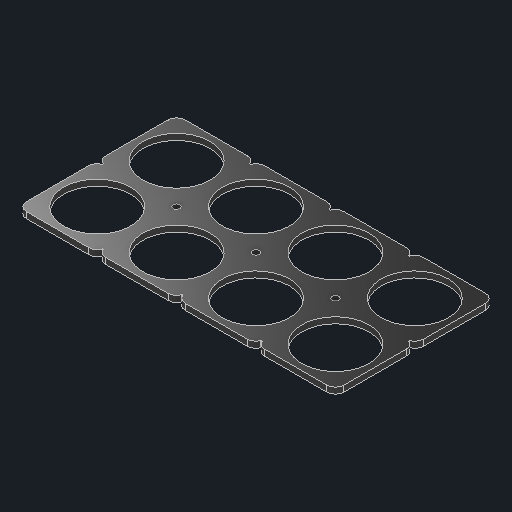
# Autodesk Inventor part: ProductsStoringGrid
Saved by Autodesk Inventor 2027.1 (Build 311270010, 270A)
## iProperties
Created: 2026-09-29
Part Number: ProductsStoringGrid
Material: MDF Medium Density Fiberboard
Document SubType Name: Modeling
Designer: SDS Scholar
Density: 0.8 g/cm^3
Appearance: Glossy - Black
Mass: 55.351 g
Surface Area: 384.534 cm^2
Volume: 69.1887 cm^3
Author: SDS Scholar
Autodesk Inventor part; units mm, degrees
ref_plane "YZ Plane" through (0, 0, 0) normal (1, 0, 0) x (0, 1, 0)
ref_plane "XZ Plane" through (0, 0, 0) normal (0, 1, 0) x (-1, 0, 0)
ref_plane "XY Plane" through (0, 0, 0) normal (0, 0, 1) x (1, 0, 0)
sketch "Sketch1" plane through (0, 0, 0) normal (0, 1, 0) x (-1, 0, 0)
  line L0 (118, 60) -> (77, 60)
  line L1 (70, 53) -> (70, 12)
  line L2 (77, 5) -> (118, 5)
  line L3 (125, 12) -> (125, 53)
  line L4 (123, 65) -> (72, 65)
  line L5 (65, 58) -> (65, 7)
  line L6 (72, 0) -> (123, 0)
  line L7 (130, 7) -> (130, 58)
  arc A0 (130, 58) -> (123, 65) centre (123, 58) ccw
  arc A1 (123, 0) -> (130, 7) centre (123, 7) ccw
  arc A2 (118, 5) -> (125, 12) centre (118, 12) ccw
  arc A3 (125, 53) -> (118, 60) centre (118, 53) ccw
  arc A4 (77, 60) -> (70, 53) centre (77, 53) ccw
  arc A5 (70, 12) -> (77, 5) centre (77, 12) ccw
  arc A6 (65, 7) -> (72, 0) centre (72, 7) ccw
  arc A7 (72, 65) -> (65, 58) centre (72, 58) ccw
  line L8 (0, 100) -> (0, -100) construction
  line L9 (100, 0) -> (-100, 0) construction
  line L10 (70, -12) -> (70, -53)
  line L11 (77, -60) -> (118, -60)
  line L12 (65, -7) -> (65, -58)
  arc A8 (77, -5) -> (70, -12) centre (77, -12) ccw
  line L13 (72, -65) -> (123, -65)
  arc A9 (72, 0) -> (65, -7) centre (72, -7) ccw
  line L14 (118, -5) -> (77, -5)
  line L15 (123, 0) -> (72, 0)
  arc A10 (130, -7) -> (123, 0) centre (123, -7) ccw
  arc A11 (65, -58) -> (72, -65) centre (72, -58) ccw
  arc A12 (70, -53) -> (77, -60) centre (77, -53) ccw
  line L16 (125, -53) -> (125, -12)
  line L17 (130, -58) -> (130, -7)
  arc A13 (125, -12) -> (118, -5) centre (118, -12) ccw
  arc A14 (118, -60) -> (125, -53) centre (118, -53) ccw
  arc A15 (123, -65) -> (130, -58) centre (123, -58) ccw
  line L18 (12, 5) -> (53, 5)
  line L19 (60, 12) -> (60, 53)
  line L20 (7, 0) -> (58, 0)
  line L21 (65, 7) -> (65, 58)
  arc A16 (5, 12) -> (12, 5) centre (12, 12) ccw
  line L22 (0, 58) -> (0, 7)
  line L23 (5, 53) -> (5, 12)
  arc A17 (60, 53) -> (53, 60) centre (53, 53) ccw
  arc A18 (65, 58) -> (58, 65) centre (58, 58) ccw
  line L24 (53, 60) -> (12, 60)
  line L25 (58, 65) -> (7, 65)
  arc A19 (53, 5) -> (60, 12) centre (53, 12) ccw
  arc A20 (7, 65) -> (0, 58) centre (7, 58) ccw
  arc A21 (12, 60) -> (5, 53) centre (12, 53) ccw
  arc A22 (58, 0) -> (65, 7) centre (58, 7) ccw
  arc A23 (0, 7) -> (7, 0) centre (7, 7) ccw
  line L26 (5, -12) -> (5, -53)
  line L27 (0, -7) -> (0, -58)
  arc A24 (5, -53) -> (12, -60) centre (12, -53) ccw
  arc A25 (0, -58) -> (7, -65) centre (7, -58) ccw
  line L28 (53, -5) -> (12, -5)
  line L29 (58, 0) -> (7, 0)
  arc A26 (60, -12) -> (53, -5) centre (53, -12) ccw
  arc A27 (65, -7) -> (58, 0) centre (58, -7) ccw
  line L30 (60, -53) -> (60, -12)
  line L31 (65, -58) -> (65, -7)
  line L32 (12, -60) -> (53, -60)
  line L33 (7, -65) -> (58, -65)
  arc A28 (53, -60) -> (60, -53) centre (53, -53) ccw
  arc A29 (12, -5) -> (5, -12) centre (12, -12) ccw
  arc A30 (58, -65) -> (65, -58) centre (58, -58) ccw
  arc A31 (7, 0) -> (0, -7) centre (7, -7) ccw
  line L34 (-53, 5) -> (-12, 5)
  line L35 (-5, 12) -> (-5, 53)
  line L36 (-58, 0) -> (-7, 0)
  line L37 (0, 7) -> (0, 58)
  arc A32 (-60, 12) -> (-53, 5) centre (-53, 12) ccw
  line L38 (-65, 58) -> (-65, 7)
  line L39 (-60, 53) -> (-60, 12)
  arc A33 (-5, 53) -> (-12, 60) centre (-12, 53) ccw
  arc A34 (0, 58) -> (-7, 65) centre (-7, 58) ccw
  line L40 (-12, 60) -> (-53, 60)
  line L41 (-7, 65) -> (-58, 65)
  arc A35 (-12, 5) -> (-5, 12) centre (-12, 12) ccw
  arc A36 (-58, 65) -> (-65, 58) centre (-58, 58) ccw
  arc A37 (-53, 60) -> (-60, 53) centre (-53, 53) ccw
  arc A38 (-7, 0) -> (0, 7) centre (-7, 7) ccw
  arc A39 (-65, 7) -> (-58, 0) centre (-58, 7) ccw
  line L42 (-60, -12) -> (-60, -53)
  line L43 (-65, -7) -> (-65, -58)
  arc A40 (-60, -53) -> (-53, -60) centre (-53, -53) ccw
  arc A41 (-65, -58) -> (-58, -65) centre (-58, -58) ccw
  line L44 (-12, -5) -> (-53, -5)
  line L45 (-7, 0) -> (-58, 0)
  arc A42 (-5, -12) -> (-12, -5) centre (-12, -12) ccw
  arc A43 (0, -7) -> (-7, 0) centre (-7, -7) ccw
  line L46 (-5, -53) -> (-5, -12)
  line L47 (0, -58) -> (0, -7)
  line L48 (-53, -60) -> (-12, -60)
  line L49 (-58, -65) -> (-7, -65)
  arc A44 (-12, -60) -> (-5, -53) centre (-12, -53) ccw
  arc A45 (-53, -5) -> (-60, -12) centre (-53, -12) ccw
  arc A46 (-7, -65) -> (0, -58) centre (-7, -58) ccw
  arc A47 (-58, 0) -> (-65, -7) centre (-58, -7) ccw
  line L50 (-118, 5) -> (-77, 5)
  line L51 (-70, 12) -> (-70, 53)
  line L52 (-123, 0) -> (-72, 0)
  line L53 (-65, 7) -> (-65, 58)
  arc A48 (-125, 12) -> (-118, 5) centre (-118, 12) ccw
  line L54 (-130, 58) -> (-130, 7)
  line L55 (-125, 53) -> (-125, 12)
  arc A49 (-70, 53) -> (-77, 60) centre (-77, 53) ccw
  arc A50 (-65, 58) -> (-72, 65) centre (-72, 58) ccw
  line L56 (-77, 60) -> (-118, 60)
  line L57 (-72, 65) -> (-123, 65)
  arc A51 (-77, 5) -> (-70, 12) centre (-77, 12) ccw
  arc A52 (-123, 65) -> (-130, 58) centre (-123, 58) ccw
  arc A53 (-118, 60) -> (-125, 53) centre (-118, 53) ccw
  arc A54 (-72, 0) -> (-65, 7) centre (-72, 7) ccw
  arc A55 (-130, 7) -> (-123, 0) centre (-123, 7) ccw
  line L58 (-125, -12) -> (-125, -53)
  line L59 (-130, -7) -> (-130, -58)
  arc A56 (-125, -53) -> (-118, -60) centre (-118, -53) ccw
  arc A57 (-130, -58) -> (-123, -65) centre (-123, -58) ccw
  line L60 (-77, -5) -> (-118, -5)
  line L61 (-72, 0) -> (-123, 0)
  arc A58 (-70, -12) -> (-77, -5) centre (-77, -12) ccw
  arc A59 (-65, -7) -> (-72, 0) centre (-72, -7) ccw
  line L62 (-70, -53) -> (-70, -12)
  line L63 (-65, -58) -> (-65, -7)
  line L64 (-118, -60) -> (-77, -60)
  line L65 (-123, -65) -> (-72, -65)
  arc A60 (-77, -60) -> (-70, -53) centre (-77, -53) ccw
  arc A61 (-118, -5) -> (-125, -12) centre (-118, -12) ccw
  arc A62 (-72, -65) -> (-65, -58) centre (-72, -58) ccw
  arc A63 (-123, 0) -> (-130, -7) centre (-123, -7) ccw
  circle A64 centre (65, 0) radius 2.75
  circle A65 centre (0, 0) radius 2.75
  circle A66 centre (-65, 0) radius 2.75
  circle A67 centre (97.5, -32.5) radius 27.5
  circle A68 centre (32.5, -32.5) radius 27.5
  circle A69 centre (-32.5, -32.5) radius 27.5
  circle A70 centre (-97.5, -32.5) radius 27.5
  circle A71 centre (97.5, 32.5) radius 27.5
  circle A72 centre (32.5, 32.5) radius 27.5
  circle A73 centre (-32.5, 32.5) radius 27.5
  circle A74 centre (-97.5, 32.5) radius 27.5
  point P0 (125, 60)
  point P1 (70, 5)
  point P2 (125, 5)
  point P3 (70, -60)
  point P4 (125, -60)
  point P5 (125, -5)
  point P6 (97.5, 0)
  point P7 (60, 5)
  point P8 (5, 5)
  point P9 (60, 60)
  point P10 (5, -60)
  point P11 (60, -5)
  point P12 (32.5, 0)
  point P13 (60, -60)
  point P14 (-5, 5)
  point P15 (-60, 5)
  point P16 (-5, 60)
  point P17 (-60, -60)
  point P18 (-5, -5)
  point P19 (-32.5, 0)
  point P20 (-5, -60)
  point P21 (-70, 5)
  point P22 (-125, 5)
  point P23 (-70, 60)
  point P24 (-125, -60)
  point P25 (-70, -5)
  point P26 (-97.5, 0)
  point P27 (-70, -60)
  point P28 (0, -32.5)
  point P29 (65, -32.5)
  point P30 (-65, -32.5)
  point P31 (123, 0)
  point P32 (0, 58)
  point P33 (-123, 0)
  point P34 (-65, -58)
  point P35 (0, -58)
  point P36 (65, -58)
  point P37 (-65, 7)
  point P38 (0, 58)
  point P39 (0, 7)
  point P40 (65, 7)
  point P41 (65, -7)
  point P42 (65, -58)
  point P43 (0, -7)
  point P44 (0, -58)
  point P45 (-65, -58)
  point P46 (-65, -7)
  point P47 (-125, 32.5)
  point P48 (-97.5, 60)
  point P49 (-70, 32.5)
  point P50 (-97.5, 5)
  point P51 (-125, -32.5)
  point P52 (-97.5, -5)
  point P53 (-70, -32.5)
  point P54 (-97.5, -60)
  point P55 (-60, -32.5)
  point P56 (-32.5, -5)
  point P57 (-5, -32.5)
  point P58 (-32.5, -60)
  point P59 (-60, 32.5)
  point P60 (-32.5, 60)
  point P61 (-5, 32.5)
  point P62 (-32.5, 5)
  point P63 (5, 32.5)
  point P64 (32.5, 60)
  point P65 (60, 32.5)
  point P66 (32.5, 5)
  point P67 (5, -32.5)
  point P68 (32.5, -5)
  point P69 (60, -32.5)
  point P70 (32.5, -60)
  point P71 (125, -32.5)
  point P72 (97.5, -60)
  point P73 (97.5, -5)
  point P74 (70, -32.5)
  point P75 (97.5, 5)
  point P76 (70, 32.5)
  point P77 (97.5, 60)
  point P78 (125, 32.5)
  dimension "d0" = 55
  dimension "d1" = 55
  dimension "d2" = 5
  dimension "d3" = 7
  dimension "d4" = 200
  dimension "d6" = 200
  dimension "d9" = 65
  dimension "d19" = 65
  dimension "d23" = 5.5
  dimension "d24" = 5.5
  dimension "d25" = 5.5
  dimension "d40" = 55
  dimension "d43" = 65
  dimension "d46" = 65
  constraints: 132 end point, 128 point on circle, 75 centre point, 50 point on line, 18 tangent, 7 equal radius, 6 midpoint, 4 horizontal, 4 parallel, 3 vertical, 3 vertical alignment, 2 coincident, 2 perpendicular, 1 horizontal alignment, 321 other
  measures "d0" distance of point (70, 5) point (125, 5)
  measures "d1" distance of point (125, 5) point (125, 60)
  measures "d2" distance between parallel lines of L3 L7
  measures "d3" radius of A0
  measures "d4" distance of L8.start L8.end
  measures "d6" distance of L9.start L9.end
  measures "d9" distance of L1.end L10.end
  measures "d19" distance of L2.start L18.start
  measures "d23" diameter of A64
  measures "d24" diameter of A65
  measures "d25" diameter of A66
  measures "d40" diameter of A67
  measures "d43" distance of A67.centre A68.centre
  measures "d46" distance of A67.centre A71.centre
extrude "Extrusion1" add sketch "Sketch1" along normal blind 5 contours A3 L3 A71 L0 | A71 L1 A4 L0 | L3 A2 L2 A71 | A71 L2 A5 L1 | A0 L7 A1 L6 A6 L5 A7 L4 | L5 A22 L20 A23 L22 A20 L25 A18 | A6 A9 A27 A22 | A10 L17 A15 L13 A11 L12 A9 L6 | A27 L12 A30 L33 A25 L27 A31 L20 | A31 A43 A38 A23 | L22 A38 L36 A39 L38 A36 L41 A34 | L27 A46 L49 A41 L43 A47 L36 A43 | A47 A59 A54 A39 | L38 A54 L52 A55 L54 A52 L57 A50 | L43 A62 L65 A57 L59 A63 L52 A59 | A8 L14 A67 L10 | A67 L11 A12 L10 | L14 A13 L16 A67 | A67 L16 A14 L11 | A16 L23 A72 L18 | A72 L19 A19 L18 | L23 A21 L24 A72 | A72 L24 A17 L19 | A29 L28 A68 L26 | A68 L32 A24 L26 | L28 A26 L30 A68 | A68 L30 A28 L32 | A32 L39 A73 L34 | A73 L35 A35 L34 | L39 A37 L40 A73 | A73 L40 A33 L35 | A45 L44 A69 L42 | A69 L48 A40 L42 | L44 A42 L46 A69 | A69 L46 A44 L48 | A48 L55 A74 L50 | A74 L51 A51 L50 | L55 A53 L56 A74 | A74 L56 A49 L51 | A61 L60 A70 L58 | A70 L64 A56 L58 | L60 A58 L62 A70 | A70 L62 A60 L64
fillet "Fillet1" radius 0.5 8 edges at (123, 2.5, 0) (65, 2.5, 58) (0, 2.5, 58) (-65, 2.5, 58) (-123, 2.5, 0) (-65, 2.5, -58) (0, 2.5, -58) (65, 2.5, -58)
equation "\"d0\" = Product_dia + GridProcutClearance"
equation "\"d1\" = Product_dia + GridProcutClearance"
equation "\"d2\" = GridBorderThickness"
equation "\"d3\" = GridBorderFillets"
equation "\"d9\" = GridTotalSize"
equation "\"d19\" = GridTotalSize"
equation "\"d40\" = Product_dia + GridProcutClearance"
equation "\"d43\" = GridTotalSize"
equation "\"d46\" = GridTotalSize"
equation "\"Product_dia\" = 50"
equation "\"GridBorderThickness\" = 5"
equation "\"GridBorderFillets\" = 7"
equation "\"GridTotalSize\" = 65"
equation "\"GridProcutClearance\" = 5"
equation "\"GridRobotClearance\" = 65"
equation "\"AluminiumExtrusionClearance\" = 35"
equation "\"BaseTotalLength\" = 885"
equation "\"WorkspaceLength\" = 515"
equation "\"WorkspaceHeight\" = 183"
equation "\"AxesBaseFillet\" = 15"
equation "\"Zaxis\" = 197"
equation "\"ProductTotalHeight\" = 45"
equation "\"VerticalStroke\" = 105"
equation "\"BackArea\" = 165"
equation "\"CylinderStroke\" = 75"
equation "\"BoxesWidth\" = 125"
equation "\"BaseWoodThickness\" = 7"
equation "\"kerf\" = 1.5"
equation "\"Kerf\" = 0.3"
equation "\"RxThickness\" = 1.8"
equation "\"support_2\" = 265"
body "Solid1"
